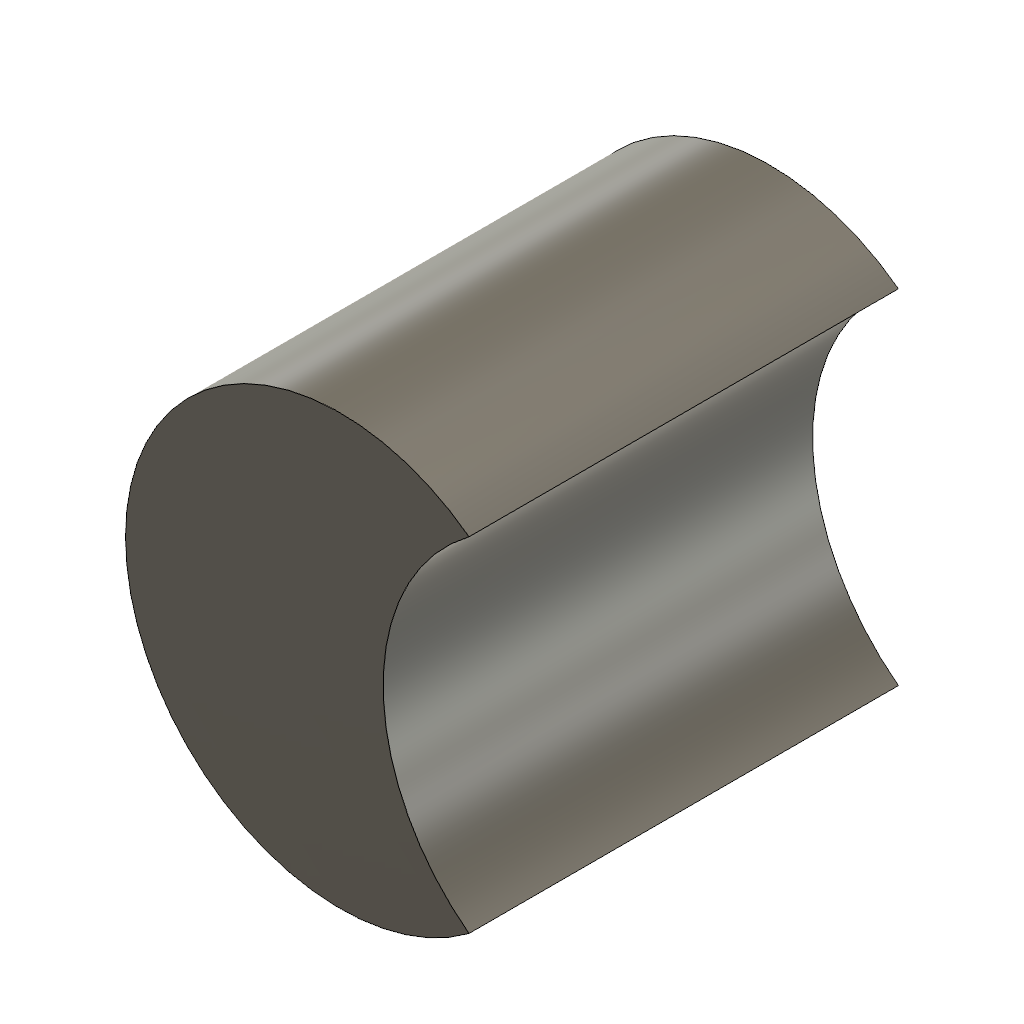
CombineCutNoKeep (Autodesk Fusion 360 design; units mm, degrees)
part number: 2026-10-20-18-22-10-510
Autodesk Fusion 360 part; units mm, degrees
sketch "SeedProfile" plane through (0, 0, 0) normal (0, 0, 1) x (1, 0, 0)
  circle A0 centre (0, 0) radius 10
extrude "SeedExtrusion" add sketch "SeedProfile" along normal blind 20 makes body 1
sketch "ToolProfile" plane through (0, 0, 0) normal (0, 0, 1) x (1, 0, 0)
  circle A0 centre (12, 0) radius 10
extrude "ToolExtrusion" add sketch "ToolProfile" along normal blind 20 separate body makes body 2
combine "ProbeCombineCutNoKeep" operation cut target body 1 tool bodies 2
